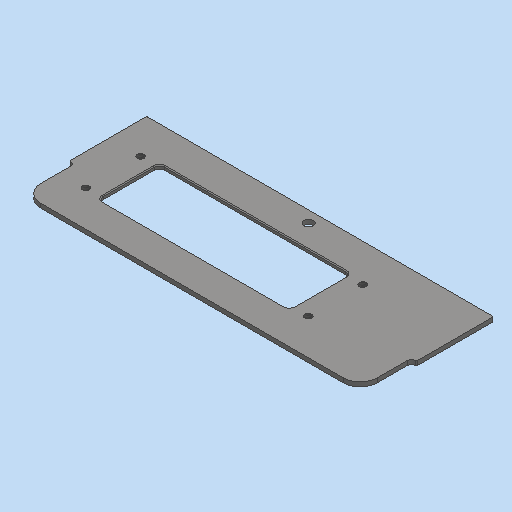
# Autodesk Inventor part: MM0861AN105_G12_103
Saved by Autodesk Inventor 2023.3 (Build 273359000, 359)
## iProperties
Part Number: MM0861AN105_G12_103
Material: 1.4301 X5CrNi18-10
Description: =<RBPARTNOTITLE2>
Document SubType Name: Blech
Designer: ric7an
Mass: 213.391 g
Surface Area: 238.969 cm^2
Volume: 27.1836 cm^3
Density: 7.85 g/cm^3
Sheet Metal Rule: Standard_mm
Appearance: Stahl - rostfrei AnP
RBCHANGEDESCRIPTION1: Erstfreigabe
RBCHANGENO1: 00
RBDOCUMENTTYPE: DRF
RBDOCUMENTVERSION: 00
RBDRAWINGMAINSCALE: 1:1
RBDRAWINGMISSINGSPEC: --
RBDRAWINGVOLUME: --
RBDSV1: 0850
RBGBDETAILS: 43274
RBGBEDGESIN1: +0,5
RBGBEDGESIN2: +0,2
RBGBEDGESOUT1: -0,3
RBGBEDGESOUT2: -0,1
RBMATERIAL: =<Material>
RBMATMEETS: --
RBMATNO: =<Part Number>
RBORGUNITRESPONSIBLE1: AnP/TEF1
RBPARTMADEOF: 2,5 x 75 x 203 (FM)
RBPARTNO: SIEHE MNR
RBPARTNOTITLE1: manufactured part
RBPARTNOTITLE2: Anfertigungsteil
RBPARTSAFETYINDICATOR: --
RBSURFACE: --
RBSURFACE2: --
RBZEDGESNORM: ISO13715:2002-06
RBZGENDIMCLASS: m
RBZGENDIMNORM: ISO 2768-1:1989-11
RBZGENGEOCLASS: H
RBZGENGEONORM: ISO 2768-2:1989-11
RBZSURFACENORM: ISO13D2:2002-02
RBZTOLERANCENORM: ISO 14405-1:2010-12
AnP_Material: =<Material>
AnP_TemplVers: 20190222
AnP_Kategorie: 1
MaxAbmaße: 2,5 x 75 x 203 (FM)
Author: ric7an
Keywords: =<RBPARTMADEOF>
Comments: =<RBSURFACE2>
Revision Number: 01
Autodesk Inventor part; units mm, degrees
ref_plane "YZ Plane" through (0, 0, 0) normal (1, 0, 0) x (0, 1, 0)
ref_plane "XZ Plane" through (0, 0, 0) normal (0, 1, 0) x (-1, 0, 0)
ref_plane "XY Plane" through (0, 0, 0) normal (0, 0, 1) x (1, 0, 0)
sketch "Skizze1" plane through (0, 0, 0) normal (0, 0, 1) x (1, 0, 0)
  line L0 (-101.5, 45) -> (101.5, 45)
  line L1 (101.5, 45) -> (101.5, 0)
  line L2 (101.5, 0) -> (-101.5, 0)
  line L3 (-101.5, 0) -> (-101.5, 45)
  line L4 (0, 60) -> (0, -45)
  line L5 (-142.1, 0) -> (142.1, 0)
  line L6 (-98.5, 0) -> (98.5, 0)
  line L7 (98.5, 0) -> (98.5, -30)
  line L8 (98.5, -30) -> (-98.5, -30)
  line L9 (-98.5, -30) -> (-98.5, 0)
  point P0 (0, 0)
  dimension "d1" = 203
  dimension "d2" = 45
  dimension "d4" = 30
  dimension "d5" = 197
  measures "d1" distance of L0.start L0.end
  measures "d2" distance of L0.end L1.end
  measures "d4" distance of L6.end L7.end
  measures "d5" distance of L7.end L8.end
extrude "Grobblech1" add sketch "Skizze1" along normal blind 2.5
fillet "Eckenrundung1" radius 10 2 edges at (-98.5, -30, 1.25) (98.5, -30, 1.25)
fillet "Eckenrundung2" radius 2.4 2 edges at (98.5, 0, 1.25) (-98.5, 0, 1.25)
sketch "Skizze2" plane through (0, 0, 2.5) normal (0, 0, 1) x (1, 0, 0)
  line L0 (0, 60) -> (0, -45) projected
  line L1 (-142.1, 0) -> (142.1, 0) projected
  line L2 (-101.5, 45) -> (101.5, 45) projected
  line L3 (88.5, -30) -> (-88.5, -30) projected
  point P0 (0, 0)
  point P1 (-83, 23)
  point P2 (-83, -9)
  point P3 (47, 23)
  point P4 (47, -9)
  dimension "d8" = 32
  dimension "d9" = 130
  dimension "d23" = 21
  dimension "d42" = 47
  constraints: 2 horizontal alignment, 2 vertical alignment
  measures "d8" distance of point (47, -9) point (47, 23)
  measures "d9" distance of point (47, 23) point (-83, 23)
  measures "d23" distance from line of L3 point (47, -9)
  measures "d42" distance from line of L0 point (47, -9)
hole "Bohrung1" at (-83, 23, 2.5) at (-83, -9, 2.5) at (47, 23, 2.5) at (47, -9, 2.5) direction (0, 0, -1) diameter 4.134 end through all thread size "M5x0.8" designation "M5" class "6H" standard "ISO Metric profile"
sketch "Skizze3" plane through (0, 0, 2.5) normal (0, 0, 1) x (1, 0, 0)
  line L0 (-74, 25) -> (38, 25)
  line L1 (38, 25) -> (38, -11)
  line L2 (38, -11) -> (-74, -11)
  line L3 (-74, -11) -> (-74, 25)
  line L4 (0, 60) -> (0, -45) projected
  line L5 (-142.1, 0) -> (142.1, 0) projected
  line L6 (-74, 7) -> (38, 7) construction
  circle A0 centre (-83, 23) radius 2.067 projected
  point P0 (0, 0)
  dimension "d18" = 36
  dimension "d19" = 112
  dimension "d20" = 16
  dimension "d41" = 9
  constraints: 10 end point, 2 midpoint, 2 parallel, 1 horizontal, 1 perpendicular
  measures "d18" distance of L0.end L1.end
  measures "d19" distance of L0.start L0.end
  measures "d20" distance from line of A0.centre L6
  measures "d41" distance from line of L3 A0.centre
extrude "Ausklinkung1" cut sketch "Skizze3" against normal blind 2.5 contours L0 L4 L5 L3 | L0 L1 L5 L4 | L5 L4 L2 L3 | L5 L1 L2 L4
fillet "Eckenrundung3" radius 3 4 edges at (-74, 25, 1.25) (-74, -11, 1.25) (38, -11, 1.25) (38, 25, 1.25)
fillet "Eckenrundung4" radius 0.5 4 edges at (101.5, 45, 1.25) (-101.5, 45, 1.25) (101.5, 0, 1.25) (-101.5, 0, 1.25)
chamfer "Fase1" distance 0.5 angle 45 16 edges at (-18, 25, 2.5) (37.1213, 24.1213, 2.5) (38, 7, 2.5) (37.1213, -10.1213, 2.5) (-18, -11, 2.5) (-73.1213, -10.1213, 2.5) (-74, 7, 2.5) (-73.1213, 24.1213, 2.5) (-18, 25, 0) (-73.1213, 24.1213, 0) (-74, 7, 0) (-73.1213, -10.1213, 0) (-18, -11, 0) (37.1213, -10.1213, 0) (38, 7, 0) (37.1213, 24.1213, 0)
sketch "Skizze4" plane through (0, 0, 2.5) normal (0, 0, 1) x (1, 0, 0)
  line L0 (88.5, -30) -> (-88.5, -30) projected
  line L1 (101.5, 44.5) -> (101.5, 0.5) projected
  line L2 (-101.5, 0.5) -> (-101.5, 44.5) projected
  point P0 (0, 0)
  point P1 (0, 38.3)
  dimension "d29" = 68.3
  dimension "d39" = 0
  measures "d29" distance from line of point (0, 38.3) L0
  measures "d39" horizontal distance of point (0, 38.3) point (0, 0)
hole "Bohrung2" at (0, 38.3, 2.5) direction (0, 0, -1) diameter 5.5 depth 2.5 tip angle 118
equation "\"d21\" = Stärke"
equation "\"d36\" = Stärke"
equation "\"d40\" = Stärke"
equation "\"Biegeradius\" = 1.2 * Stärke"
equation "\"BreiteBiegungsfreistellung\" = Stärke"
equation "\"TiefeBiegungsfreistellung\" = 0.5 * Stärke"
equation "\"MinimalRest\" = 2 * Stärke"
equation "\"Übergangsradius\" = Biegeradius"
equation "\"JacobiRadiusGröße\" = Biegeradius"
equation "\"Abstandsgröße\" = Stärke"
equation "\"d3\" = Biegeradius"
equation "\"Stärke\" = 2.5"
